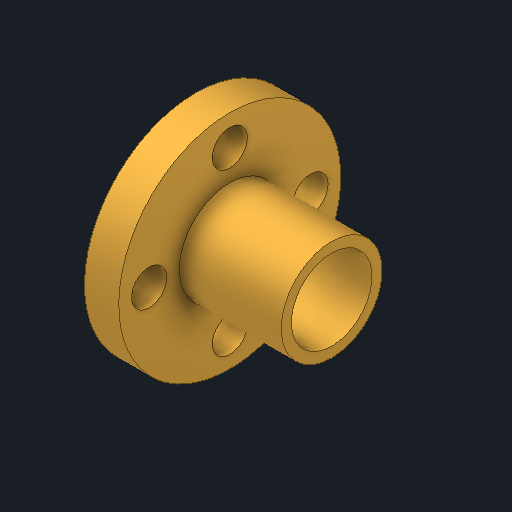
# Autodesk Inventor part: T8_LeadNut
Saved by Autodesk Inventor 2026.2 (Build 302298000, 298)
## iProperties
Created: 2025-11-14
Part Number: T8_LeadNut
Material: 황동, 연질 노란색
Document SubType Name: Modeling
Designer: work
Density: 8.47 g/cm^3
Appearance: 황동 - 새틴
Author: work
Autodesk Inventor part; units mm, degrees
ref_plane "YZ Plane" through (0, 0, 0) normal (1, 0, 0) x (0, 1, 0)
ref_plane "XZ Plane" through (0, 0, 0) normal (0, 1, 0) x (-1, 0, 0)
ref_plane "XY Plane" through (0, 0, 0) normal (0, 0, 1) x (1, 0, 0)
sketch "스케치1" plane through (0, 0, 0) normal (0, 0, 1) x (1, 0, 0)
  line L0 (0, 0) -> (15, 0)
  line L1 (15, 0) -> (15, 5)
  line L2 (15, 5) -> (0, 5)
  line L3 (0, 5) -> (0, 0)
  line L4 (1.5, 5) -> (1.5, 11)
  line L5 (1.5, 11) -> (4.9, 11)
  line L6 (4.9, 11) -> (4.9, 5)
  line L7 (0, 4) -> (15, 4)
  point P0 (3.2, 11)
  dimension "d0" = 8
  dimension "d1" = 10
  dimension "d2" = 22
  dimension "d3" = 3.4
  dimension "d4" = 1.5
  dimension "d5" = 15
  constraints: 16 end point, 6 perpendicular, 4 point on line, 1 horizontal, 1 midpoint, 1 vertical
  measures "d0" diameter of L7 L0
  measures "d1" diameter of L2 L0
  measures "d2" diameter of point (3.2, 11) L0
  measures "d3" distance of L4.end L5.end
  measures "d4" distance from line of L2.end L4
  measures "d5" distance of L1.end L2.end
revolve "회전1" add sketch "스케치1" angle 360 about axis through (0, 0, 0) along (1, 0, 0) contours L3 L2 L1 L7 | L4 L5 L6 L2
sketch "스케치2" plane through (1.5, 0, 0) normal (-1, 0, 0) x (0, 0, 1)
  circle A0 centre (-8, 0) radius 1.75
  circle A1 centre (0, 0) radius 5 projected
  circle A2 centre (0, 0) radius 11 projected
  line L0 (0, 0) -> (-8, 0) construction
  circle A3 centre (0, -8) radius 1.75
  circle A4 centre (8, 0) radius 1.75
  circle A5 centre (0, 8) radius 1.75
  point P0 (0, 0)
  dimension "d7" = 3.5
  dimension "d9" = 8
  dimension "d12" = 360
  constraints: 4 centre point, 2 end point, 1 horizontal, 9 other
  measures "d7" diameter of A0
  measures "d9" distance of point (0, 0) L0.end
extrude "돌출1" cut sketch "스케치2" against normal blind 10 contours A0 | A3 | A4 | A5
